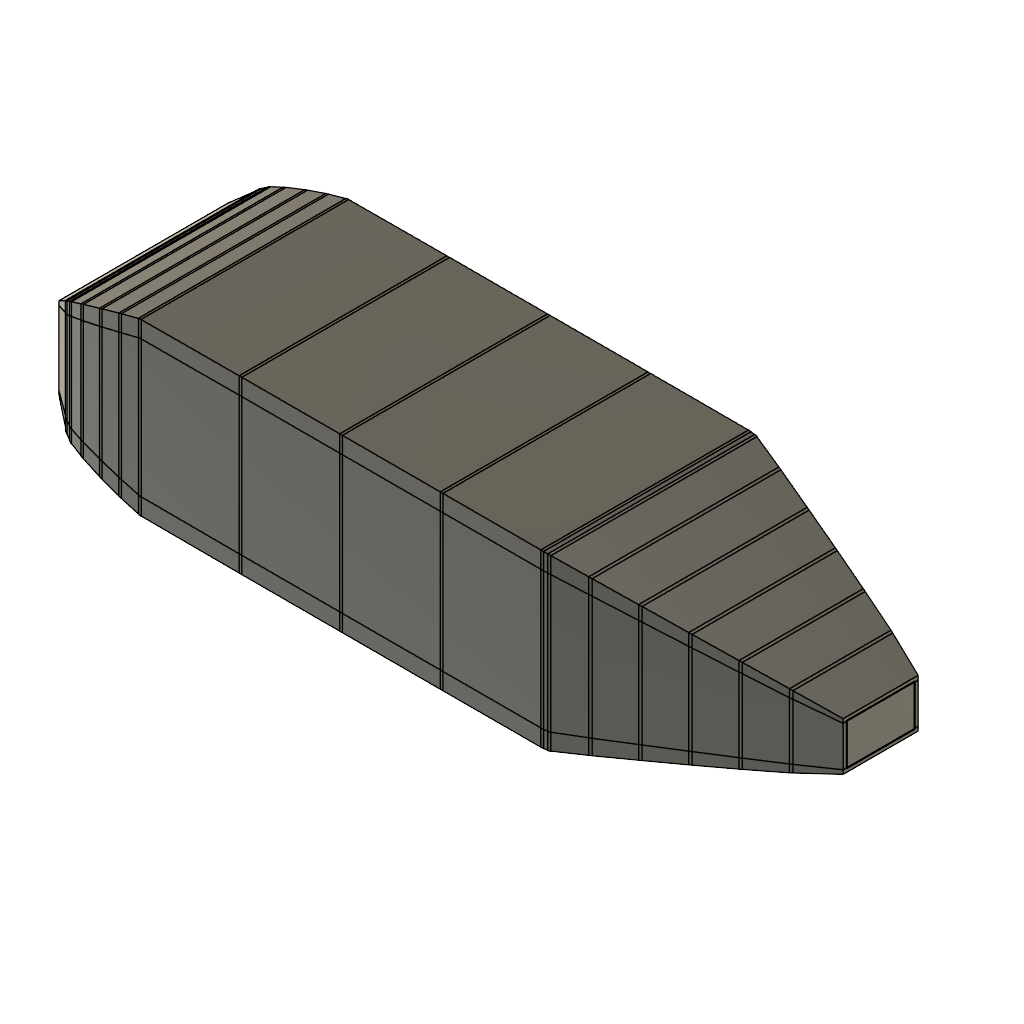
Magnetide-B-printable (Autodesk Fusion 360 design; units mm, degrees)
part number: 2026-10-21-01-27-55-911
Autodesk Fusion 360 part; units mm, degrees
(part 1 of 2)
ref_plane "WorkPlane1" through (60, 0, 0) normal (1, 0, 0) x (0, 1, 0)
sketch "plate_a" plane through (60, 0, 0) normal (1, 0, 0) x (0, 0, -1)
  line L0 (-7, -21.85) -> (-7, 21.85)
  line L1 (-7, 21.85) -> (-10.5, 21.85)
  line L2 (-10.5, 21.85) -> (-10.5, 22.75)
  line L3 (-10.5, 22.75) -> (-7, 22.75)
  line L4 (-7, 22.75) -> (-7, 23.5)
  line L5 (-7, 23.5) -> (-18.5, 23.5)
  line L6 (-18.5, 23.5) -> (-18.5, 20.3)
  line L7 (-18.5, 20.3) -> (-8.5, 20.3)
  line L8 (-8.5, 20.3) -> (-8.5, -20.3)
  line L9 (-8.5, -20.3) -> (-18.5, -20.3)
  line L10 (-18.5, -20.3) -> (-18.5, -23.5)
  line L11 (-18.5, -23.5) -> (-7, -23.5)
  line L12 (-7, -23.5) -> (-7, -22.75)
  line L13 (-7, -22.75) -> (-10.5, -22.75)
  line L14 (-10.5, -22.75) -> (-10.5, -21.85)
  line L15 (-10.5, -21.85) -> (-7, -21.85)
extrude "Extrude1" add sketch "plate_a" along normal mid plane 120 makes body 1
ref_plane "WorkPlane2" through (60, 0, 0) normal (1, 0, 0) x (0, 1, 0)
sketch "plate_b" plane through (60, 0, 0) normal (1, 0, 0) x (0, 0, -1)
  line L0 (7, -21.85) -> (7, 21.85)
  line L1 (7, 21.85) -> (10.5, 21.85)
  line L2 (10.5, 21.85) -> (10.5, 22.75)
  line L3 (10.5, 22.75) -> (7, 22.75)
  line L4 (7, 22.75) -> (7, 23.5)
  line L5 (7, 23.5) -> (18.5, 23.5)
  line L6 (18.5, 23.5) -> (18.5, 20.3)
  line L7 (18.5, 20.3) -> (8.5, 20.3)
  line L8 (8.5, 20.3) -> (8.5, -20.3)
  line L9 (8.5, -20.3) -> (18.5, -20.3)
  line L10 (18.5, -20.3) -> (18.5, -23.5)
  line L11 (18.5, -23.5) -> (7, -23.5)
  line L12 (7, -23.5) -> (7, -22.75)
  line L13 (7, -22.75) -> (10.5, -22.75)
  line L14 (10.5, -22.75) -> (10.5, -21.85)
  line L15 (10.5, -21.85) -> (7, -21.85)
extrude "Extrude2" add sketch "plate_b" along normal mid plane 120 separate body makes body 2
ref_plane "WorkPlane3" through (0, -22.7, 0) normal (0, 1, 0) x (0, 0, 1)
sketch "rail_left" plane through (0, -22.7, 0) normal (0, 1, 0) x (1, 0, 0)
  line L0 (0, 7) -> (120, 7)
  line L1 (120, 7) -> (120, -7)
  line L2 (120, -7) -> (0, -7)
  line L3 (0, -7) -> (0, 7)
extrude "Extrude3" add sketch "rail_left" along normal mid plane 1.6 separate body makes body 3
ref_plane "WorkPlane4" through (0, 22.7, 0) normal (0, 1, 0) x (0, 0, 1)
sketch "rail_right" plane through (0, 22.7, 0) normal (0, 1, 0) x (1, 0, 0)
  line L0 (0, 7) -> (120, 7)
  line L1 (120, 7) -> (120, -7)
  line L2 (120, -7) -> (0, -7)
  line L3 (0, -7) -> (0, 7)
extrude "Extrude4" add sketch "rail_right" along normal mid plane 1.6 separate body makes body 4
ref_plane "WorkPlane5" through (-20, 0, 0) normal (1, 0, 0) x (0, 1, 0)
sketch "Sketch5" plane through (-20, 0, 0) normal (1, 0, 0) x (0, 0, -1)
  line L0 (-12, -23.5) -> (-10.5, -23.5)
  line L1 (-10.5, -23.5) -> (-10.5, 23.5)
  line L2 (-10.5, 23.5) -> (-12, 23.5)
  line L3 (-12, 23.5) -> (-12, -23.5)
ref_plane "WorkPlane6" through (-15.6, 0, 0) normal (1, 0, 0) x (0, 1, 0)
sketch "Sketch6" plane through (-15.6, 0, 0) normal (1, 0, 0) x (0, 0, -1)
  line L0 (-10.6294, -23.5) -> (-9.1294, -23.5)
  line L1 (-9.1294, -23.5) -> (-9.1294, 23.5)
  line L2 (-9.1294, 23.5) -> (-10.6294, 23.5)
  line L3 (-10.6294, 23.5) -> (-10.6294, -23.5)
loft "Loft1" add profiles "Sketch5", "Sketch6" section 1 section 2 separate body makes body 5
ref_plane "WorkPlane7" through (-16.4, 0, 0) normal (1, 0, 0) x (0, 1, 0)
sketch "Sketch7" plane through (-16.4, 0, 0) normal (1, 0, 0) x (0, 0, -1)
  line L0 (-10.8534, -23.5) -> (-9.3534, -23.5)
  line L1 (-9.3534, -23.5) -> (-9.3534, 23.5)
  line L2 (-9.3534, 23.5) -> (-10.8534, 23.5)
  line L3 (-10.8534, 23.5) -> (-10.8534, -23.5)
ref_plane "WorkPlane8" through (-11.6, 0, 0) normal (1, 0, 0) x (0, 1, 0)
sketch "Sketch8" plane through (-11.6, 0, 0) normal (1, 0, 0) x (0, 0, -1)
  line L0 (-9.6774, -23.5) -> (-8.1774, -23.5)
  line L1 (-8.1774, -23.5) -> (-8.1774, 23.5)
  line L2 (-8.1774, 23.5) -> (-9.6774, 23.5)
  line L3 (-9.6774, 23.5) -> (-9.6774, -23.5)
loft "Loft2" add profiles "Sketch7", "Sketch8" section 1 section 2 separate body makes body 6
ref_plane "WorkPlane9" through (-12.4, 0, 0) normal (1, 0, 0) x (0, 1, 0)
sketch "Sketch9" plane through (-12.4, 0, 0) normal (1, 0, 0) x (0, 0, -1)
  line L0 (-9.8454, -23.5) -> (-8.3454, -23.5)
  line L1 (-8.3454, -23.5) -> (-8.3454, 23.5)
  line L2 (-8.3454, 23.5) -> (-9.8454, 23.5)
  line L3 (-9.8454, 23.5) -> (-9.8454, -23.5)
ref_plane "WorkPlane10" through (-7.6, 0, 0) normal (1, 0, 0) x (0, 1, 0)
sketch "Sketch10" plane through (-7.6, 0, 0) normal (1, 0, 0) x (0, 0, -1)
  line L0 (-9.0054, -23.5) -> (-7.5054, -23.5)
  line L1 (-7.5054, -23.5) -> (-7.5054, 23.5)
  line L2 (-7.5054, 23.5) -> (-9.0054, 23.5)
  line L3 (-9.0054, 23.5) -> (-9.0054, -23.5)
loft "Loft3" add profiles "Sketch9", "Sketch10" section 1 section 2 separate body makes body 7
ref_plane "WorkPlane11" through (-8.4, 0, 0) normal (1, 0, 0) x (0, 1, 0)
sketch "Sketch11" plane through (-8.4, 0, 0) normal (1, 0, 0) x (0, 0, -1)
  line L0 (-9.1174, -23.5) -> (-7.6174, -23.5)
  line L1 (-7.6174, -23.5) -> (-7.6174, 23.5)
  line L2 (-7.6174, 23.5) -> (-9.1174, 23.5)
  line L3 (-9.1174, 23.5) -> (-9.1174, -23.5)
ref_plane "WorkPlane12" through (-3.6, 0, 0) normal (1, 0, 0) x (0, 1, 0)
sketch "Sketch12" plane through (-3.6, 0, 0) normal (1, 0, 0) x (0, 0, -1)
  line L0 (-8.6134, -23.5) -> (-7.1134, -23.5)
  line L1 (-7.1134, -23.5) -> (-7.1134, 23.5)
  line L2 (-7.1134, 23.5) -> (-8.6134, 23.5)
  line L3 (-8.6134, 23.5) -> (-8.6134, -23.5)
loft "Loft4" add profiles "Sketch11", "Sketch12" section 1 section 2 separate body makes body 8
ref_plane "WorkPlane13" through (-4.4, 0, 0) normal (1, 0, 0) x (0, 1, 0)
sketch "Sketch13" plane through (-4.4, 0, 0) normal (1, 0, 0) x (0, 0, -1)
  line L0 (-8.6694, -23.5) -> (-7.1694, -23.5)
  line L1 (-7.1694, -23.5) -> (-7.1694, 23.5)
  line L2 (-7.1694, 23.5) -> (-8.6694, 23.5)
  line L3 (-8.6694, 23.5) -> (-8.6694, -23.5)
ref_plane "WorkPlane14" through (0, 0, 0) normal (1, 0, 0) x (0, 1, 0)
sketch "Sketch14" plane through (0, 0, 0) normal (1, 0, 0) x (0, 0, -1)
  line L0 (-8.5, -23.5) -> (-7, -23.5)
  line L1 (-7, -23.5) -> (-7, 23.5)
  line L2 (-7, 23.5) -> (-8.5, 23.5)
  line L3 (-8.5, 23.5) -> (-8.5, -23.5)
loft "Loft5" add profiles "Sketch13", "Sketch14" section 1 section 2 separate body makes body 9
ref_plane "WorkPlane15" through (-20, 0, 0) normal (1, 0, 0) x (0, 1, 0)
sketch "Sketch15" plane through (-20, 0, 0) normal (1, 0, 0) x (0, 0, -1)
  line L0 (10.5, -23.5) -> (12, -23.5)
  line L1 (12, -23.5) -> (12, 23.5)
  line L2 (12, 23.5) -> (10.5, 23.5)
  line L3 (10.5, 23.5) -> (10.5, -23.5)
ref_plane "WorkPlane16" through (-15.6, 0, 0) normal (1, 0, 0) x (0, 1, 0)
sketch "Sketch16" plane through (-15.6, 0, 0) normal (1, 0, 0) x (0, 0, -1)
  line L0 (9.1294, -23.5) -> (10.6294, -23.5)
  line L1 (10.6294, -23.5) -> (10.6294, 23.5)
  line L2 (10.6294, 23.5) -> (9.1294, 23.5)
  line L3 (9.1294, 23.5) -> (9.1294, -23.5)
loft "Loft6" add profiles "Sketch15", "Sketch16" section 1 section 2 separate body makes body 10
ref_plane "WorkPlane17" through (-16.4, 0, 0) normal (1, 0, 0) x (0, 1, 0)
sketch "Sketch17" plane through (-16.4, 0, 0) normal (1, 0, 0) x (0, 0, -1)
  line L0 (9.3534, -23.5) -> (10.8534, -23.5)
  line L1 (10.8534, -23.5) -> (10.8534, 23.5)
  line L2 (10.8534, 23.5) -> (9.3534, 23.5)
  line L3 (9.3534, 23.5) -> (9.3534, -23.5)
ref_plane "WorkPlane18" through (-11.6, 0, 0) normal (1, 0, 0) x (0, 1, 0)
sketch "Sketch18" plane through (-11.6, 0, 0) normal (1, 0, 0) x (0, 0, -1)
  line L0 (8.1774, -23.5) -> (9.6774, -23.5)
  line L1 (9.6774, -23.5) -> (9.6774, 23.5)
  line L2 (9.6774, 23.5) -> (8.1774, 23.5)
  line L3 (8.1774, 23.5) -> (8.1774, -23.5)
loft "Loft7" add profiles "Sketch17", "Sketch18" section 1 section 2 separate body makes body 11
ref_plane "WorkPlane19" through (-12.4, 0, 0) normal (1, 0, 0) x (0, 1, 0)
sketch "Sketch19" plane through (-12.4, 0, 0) normal (1, 0, 0) x (0, 0, -1)
  line L0 (8.3454, -23.5) -> (9.8454, -23.5)
  line L1 (9.8454, -23.5) -> (9.8454, 23.5)
  line L2 (9.8454, 23.5) -> (8.3454, 23.5)
  line L3 (8.3454, 23.5) -> (8.3454, -23.5)
ref_plane "WorkPlane20" through (-7.6, 0, 0) normal (1, 0, 0) x (0, 1, 0)
sketch "Sketch20" plane through (-7.6, 0, 0) normal (1, 0, 0) x (0, 0, -1)
  line L0 (7.5054, -23.5) -> (9.0054, -23.5)
  line L1 (9.0054, -23.5) -> (9.0054, 23.5)
  line L2 (9.0054, 23.5) -> (7.5054, 23.5)
  line L3 (7.5054, 23.5) -> (7.5054, -23.5)
loft "Loft8" add profiles "Sketch19", "Sketch20" section 1 section 2 separate body makes body 12
ref_plane "WorkPlane21" through (-8.4, 0, 0) normal (1, 0, 0) x (0, 1, 0)
sketch "Sketch21" plane through (-8.4, 0, 0) normal (1, 0, 0) x (0, 0, -1)
  line L0 (7.6174, -23.5) -> (9.1174, -23.5)
  line L1 (9.1174, -23.5) -> (9.1174, 23.5)
  line L2 (9.1174, 23.5) -> (7.6174, 23.5)
  line L3 (7.6174, 23.5) -> (7.6174, -23.5)
ref_plane "WorkPlane22" through (-3.6, 0, 0) normal (1, 0, 0) x (0, 1, 0)
sketch "Sketch22" plane through (-3.6, 0, 0) normal (1, 0, 0) x (0, 0, -1)
  line L0 (7.1134, -23.5) -> (8.6134, -23.5)
  line L1 (8.6134, -23.5) -> (8.6134, 23.5)
  line L2 (8.6134, 23.5) -> (7.1134, 23.5)
  line L3 (7.1134, 23.5) -> (7.1134, -23.5)
loft "Loft9" add profiles "Sketch21", "Sketch22" section 1 section 2 separate body makes body 13
ref_plane "WorkPlane23" through (-4.4, 0, 0) normal (1, 0, 0) x (0, 1, 0)
sketch "Sketch23" plane through (-4.4, 0, 0) normal (1, 0, 0) x (0, 0, -1)
  line L0 (7.1694, -23.5) -> (8.6694, -23.5)
  line L1 (8.6694, -23.5) -> (8.6694, 23.5)
  line L2 (8.6694, 23.5) -> (7.1694, 23.5)
  line L3 (7.1694, 23.5) -> (7.1694, -23.5)
ref_plane "WorkPlane24" through (0, 0, 0) normal (1, 0, 0) x (0, 1, 0)
sketch "Sketch24" plane through (0, 0, 0) normal (1, 0, 0) x (0, 0, -1)
  line L0 (7, -23.5) -> (8.5, -23.5)
  line L1 (8.5, -23.5) -> (8.5, 23.5)
  line L2 (8.5, 23.5) -> (7, 23.5)
  line L3 (7, 23.5) -> (7, -23.5)
loft "Loft10" add profiles "Sketch23", "Sketch24" section 1 section 2 separate body makes body 14
ref_plane "WorkPlane25" through (-20, 0, 0) normal (1, 0, 0) x (0, 1, 0)
sketch "Sketch25" plane through (-20, 0, 0) normal (1, 0, 0) x (0, 0, -1)
  line L0 (-10.5, -23.5) -> (10.5, -23.5)
  line L1 (10.5, -23.5) -> (10.5, -21.5)
  line L2 (10.5, -21.5) -> (-10.5, -21.5)
  line L3 (-10.5, -21.5) -> (-10.5, -23.5)
ref_plane "WorkPlane26" through (-15.6, 0, 0) normal (1, 0, 0) x (0, 1, 0)
sketch "Sketch26" plane through (-15.6, 0, 0) normal (1, 0, 0) x (0, 0, -1)
  line L0 (-9.1294, -23.5) -> (9.1294, -23.5)
  line L1 (9.1294, -23.5) -> (9.1294, -21.5)
  line L2 (9.1294, -21.5) -> (-9.1294, -21.5)
  line L3 (-9.1294, -21.5) -> (-9.1294, -23.5)
loft "Loft11" add profiles "Sketch25", "Sketch26" section 1 section 2 separate body makes body 15
ref_plane "WorkPlane27" through (-16.4, 0, 0) normal (1, 0, 0) x (0, 1, 0)
sketch "Sketch27" plane through (-16.4, 0, 0) normal (1, 0, 0) x (0, 0, -1)
  line L0 (-9.3534, -23.5) -> (9.3534, -23.5)
  line L1 (9.3534, -23.5) -> (9.3534, -21.5)
  line L2 (9.3534, -21.5) -> (-9.3534, -21.5)
  line L3 (-9.3534, -21.5) -> (-9.3534, -23.5)
ref_plane "WorkPlane28" through (-11.6, 0, 0) normal (1, 0, 0) x (0, 1, 0)
sketch "Sketch28" plane through (-11.6, 0, 0) normal (1, 0, 0) x (0, 0, -1)
  line L0 (-8.1774, -23.5) -> (8.1774, -23.5)
  line L1 (8.1774, -23.5) -> (8.1774, -21.5)
  line L2 (8.1774, -21.5) -> (-8.1774, -21.5)
  line L3 (-8.1774, -21.5) -> (-8.1774, -23.5)
loft "Loft12" add profiles "Sketch27", "Sketch28" section 1 section 2 separate body makes body 16
ref_plane "WorkPlane29" through (-12.4, 0, 0) normal (1, 0, 0) x (0, 1, 0)
sketch "Sketch29" plane through (-12.4, 0, 0) normal (1, 0, 0) x (0, 0, -1)
  line L0 (-8.3454, -23.5) -> (8.3454, -23.5)
  line L1 (8.3454, -23.5) -> (8.3454, -21.5)
  line L2 (8.3454, -21.5) -> (-8.3454, -21.5)
  line L3 (-8.3454, -21.5) -> (-8.3454, -23.5)
ref_plane "WorkPlane30" through (-7.6, 0, 0) normal (1, 0, 0) x (0, 1, 0)
sketch "Sketch30" plane through (-7.6, 0, 0) normal (1, 0, 0) x (0, 0, -1)
  line L0 (-7.5054, -23.5) -> (7.5054, -23.5)
  line L1 (7.5054, -23.5) -> (7.5054, -21.5)
  line L2 (7.5054, -21.5) -> (-7.5054, -21.5)
  line L3 (-7.5054, -21.5) -> (-7.5054, -23.5)
loft "Loft13" add profiles "Sketch29", "Sketch30" section 1 section 2 separate body makes body 17
ref_plane "WorkPlane31" through (-8.4, 0, 0) normal (1, 0, 0) x (0, 1, 0)
sketch "Sketch31" plane through (-8.4, 0, 0) normal (1, 0, 0) x (0, 0, -1)
  line L0 (-7.6174, -23.5) -> (7.6174, -23.5)
  line L1 (7.6174, -23.5) -> (7.6174, -21.5)
  line L2 (7.6174, -21.5) -> (-7.6174, -21.5)
  line L3 (-7.6174, -21.5) -> (-7.6174, -23.5)
ref_plane "WorkPlane32" through (-3.6, 0, 0) normal (1, 0, 0) x (0, 1, 0)
sketch "Sketch32" plane through (-3.6, 0, 0) normal (1, 0, 0) x (0, 0, -1)
  line L0 (-7.1134, -23.5) -> (7.1134, -23.5)
  line L1 (7.1134, -23.5) -> (7.1134, -21.5)
  line L2 (7.1134, -21.5) -> (-7.1134, -21.5)
  line L3 (-7.1134, -21.5) -> (-7.1134, -23.5)
loft "Loft14" add profiles "Sketch31", "Sketch32" section 1 section 2 separate body makes body 18
ref_plane "WorkPlane33" through (-4.4, 0, 0) normal (1, 0, 0) x (0, 1, 0)
sketch "Sketch33" plane through (-4.4, 0, 0) normal (1, 0, 0) x (0, 0, -1)
  line L0 (-7.1694, -23.5) -> (7.1694, -23.5)
  line L1 (7.1694, -23.5) -> (7.1694, -21.5)
  line L2 (7.1694, -21.5) -> (-7.1694, -21.5)
  line L3 (-7.1694, -21.5) -> (-7.1694, -23.5)
ref_plane "WorkPlane34" through (0, 0, 0) normal (1, 0, 0) x (0, 1, 0)
sketch "Sketch34" plane through (0, 0, 0) normal (1, 0, 0) x (0, 0, -1)
  line L0 (-7, -23.5) -> (7, -23.5)
  line L1 (7, -23.5) -> (7, -21.5)
  line L2 (7, -21.5) -> (-7, -21.5)
  line L3 (-7, -21.5) -> (-7, -23.5)
loft "Loft15" add profiles "Sketch33", "Sketch34" section 1 section 2 separate body makes body 19
ref_plane "WorkPlane35" through (-20, 0, 0) normal (1, 0, 0) x (0, 1, 0)
sketch "Sketch35" plane through (-20, 0, 0) normal (1, 0, 0) x (0, 0, -1)
  line L0 (-10.5, 21.5) -> (10.5, 21.5)
  line L1 (10.5, 21.5) -> (10.5, 23.5)
  line L2 (10.5, 23.5) -> (-10.5, 23.5)
  line L3 (-10.5, 23.5) -> (-10.5, 21.5)
ref_plane "WorkPlane36" through (-15.6, 0, 0) normal (1, 0, 0) x (0, 1, 0)
sketch "Sketch36" plane through (-15.6, 0, 0) normal (1, 0, 0) x (0, 0, -1)
  line L0 (-9.1294, 21.5) -> (9.1294, 21.5)
  line L1 (9.1294, 21.5) -> (9.1294, 23.5)
  line L2 (9.1294, 23.5) -> (-9.1294, 23.5)
  line L3 (-9.1294, 23.5) -> (-9.1294, 21.5)
loft "Loft16" add profiles "Sketch35", "Sketch36" section 1 section 2 separate body makes body 20
ref_plane "WorkPlane37" through (-16.4, 0, 0) normal (1, 0, 0) x (0, 1, 0)
sketch "Sketch37" plane through (-16.4, 0, 0) normal (1, 0, 0) x (0, 0, -1)
  line L0 (-9.3534, 21.5) -> (9.3534, 21.5)
  line L1 (9.3534, 21.5) -> (9.3534, 23.5)
  line L2 (9.3534, 23.5) -> (-9.3534, 23.5)
  line L3 (-9.3534, 23.5) -> (-9.3534, 21.5)
ref_plane "WorkPlane38" through (-11.6, 0, 0) normal (1, 0, 0) x (0, 1, 0)
sketch "Sketch38" plane through (-11.6, 0, 0) normal (1, 0, 0) x (0, 0, -1)
  line L0 (-8.1774, 21.5) -> (8.1774, 21.5)
  line L1 (8.1774, 21.5) -> (8.1774, 23.5)
  line L2 (8.1774, 23.5) -> (-8.1774, 23.5)
  line L3 (-8.1774, 23.5) -> (-8.1774, 21.5)
loft "Loft17" add profiles "Sketch37", "Sketch38" section 1 section 2 separate body makes body 21
ref_plane "WorkPlane39" through (-12.4, 0, 0) normal (1, 0, 0) x (0, 1, 0)
sketch "Sketch39" plane through (-12.4, 0, 0) normal (1, 0, 0) x (0, 0, -1)
  line L0 (-8.3454, 21.5) -> (8.3454, 21.5)
  line L1 (8.3454, 21.5) -> (8.3454, 23.5)
  line L2 (8.3454, 23.5) -> (-8.3454, 23.5)
  line L3 (-8.3454, 23.5) -> (-8.3454, 21.5)
ref_plane "WorkPlane40" through (-7.6, 0, 0) normal (1, 0, 0) x (0, 1, 0)
sketch "Sketch40" plane through (-7.6, 0, 0) normal (1, 0, 0) x (0, 0, -1)
  line L0 (-7.5054, 21.5) -> (7.5054, 21.5)
  line L1 (7.5054, 21.5) -> (7.5054, 23.5)
  line L2 (7.5054, 23.5) -> (-7.5054, 23.5)
  line L3 (-7.5054, 23.5) -> (-7.5054, 21.5)
loft "Loft18" add profiles "Sketch39", "Sketch40" section 1 section 2 separate body makes body 22
ref_plane "WorkPlane41" through (-8.4, 0, 0) normal (1, 0, 0) x (0, 1, 0)
sketch "Sketch41" plane through (-8.4, 0, 0) normal (1, 0, 0) x (0, 0, -1)
  line L0 (-7.6174, 21.5) -> (7.6174, 21.5)
  line L1 (7.6174, 21.5) -> (7.6174, 23.5)
  line L2 (7.6174, 23.5) -> (-7.6174, 23.5)
  line L3 (-7.6174, 23.5) -> (-7.6174, 21.5)
ref_plane "WorkPlane42" through (-3.6, 0, 0) normal (1, 0, 0) x (0, 1, 0)
sketch "Sketch42" plane through (-3.6, 0, 0) normal (1, 0, 0) x (0, 0, -1)
  line L0 (-7.1134, 21.5) -> (7.1134, 21.5)
  line L1 (7.1134, 21.5) -> (7.1134, 23.5)
  line L2 (7.1134, 23.5) -> (-7.1134, 23.5)
  line L3 (-7.1134, 23.5) -> (-7.1134, 21.5)
loft "Loft19" add profiles "Sketch41", "Sketch42" section 1 section 2 separate body makes body 23
ref_plane "WorkPlane43" through (-4.4, 0, 0) normal (1, 0, 0) x (0, 1, 0)
sketch "Sketch43" plane through (-4.4, 0, 0) normal (1, 0, 0) x (0, 0, -1)
  line L0 (-7.1694, 21.5) -> (7.1694, 21.5)
  line L1 (7.1694, 21.5) -> (7.1694, 23.5)
  line L2 (7.1694, 23.5) -> (-7.1694, 23.5)
  line L3 (-7.1694, 23.5) -> (-7.1694, 21.5)
ref_plane "WorkPlane44" through (0, 0, 0) normal (1, 0, 0) x (0, 1, 0)
sketch "Sketch44" plane through (0, 0, 0) normal (1, 0, 0) x (0, 0, -1)
  line L0 (-7, 21.5) -> (7, 21.5)
  line L1 (7, 21.5) -> (7, 23.5)
  line L2 (7, 23.5) -> (-7, 23.5)
  line L3 (-7, 23.5) -> (-7, 21.5)
loft "Loft20" add profiles "Sketch43", "Sketch44" section 1 section 2 separate body makes body 24
ref_plane "WorkPlane45" through (-21, 0, 0) normal (1, 0, 0) x (0, 1, 0)
sketch "front_flange" plane through (-21, 0, 0) normal (1, 0, 0) x (0, 0, -1)
  line L0 (-14, -25.5) -> (14, -25.5)
  line L1 (14, -25.5) -> (14, 25.5)
  line L2 (14, 25.5) -> (-14, 25.5)
  line L3 (-14, 25.5) -> (-14, -25.5)
  line L4 (-10.5, -23.5) -> (-10.5, 23.5)
  line L5 (-10.5, 23.5) -> (10.5, 23.5)
  line L6 (10.5, 23.5) -> (10.5, -23.5)
  line L7 (10.5, -23.5) -> (-10.5, -23.5)
extrude "Extrude5" add sketch "front_flange" along normal mid plane 2 separate body makes body 25
ref_plane "WorkPlane46" through (121, 0, 0) normal (1, 0, 0) x (0, 1, 0)
sketch "rear_cap" plane through (121, 0, 0) normal (1, 0, 0) x (0, 0, -1)
  line L0 (-18.4, -25.5) -> (18.4, -25.5)
  line L1 (18.4, -25.5) -> (18.4, 25.5)
  line L2 (18.4, 25.5) -> (-18.4, 25.5)
  line L3 (-18.4, 25.5) -> (-18.4, -25.5)
  line L4 (-10.6, -23.6) -> (10.6, -23.6)
  line L5 (10.6, -23.6) -> (10.6, 23.6)
  line L6 (10.6, 23.6) -> (-10.6, 23.6)
  line L7 (-10.6, 23.6) -> (-10.6, -23.6)
extrude "Extrude6" add sketch "rear_cap" along normal mid plane 2 separate body makes body 26
ref_plane "WorkPlane47" through (-30, 0, 0) normal (1, 0, 0) x (0, 1, 0)
sketch "Sketch47" plane through (-30, 0, 0) normal (1, 0, 0) x (0, 0, -1)
  line L0 (-12.2, -25.2) -> (-11, -25.2)
  line L1 (-11, -25.2) -> (-11, 25.2)
  line L2 (-11, 25.2) -> (-12.2, 25.2)
  line L3 (-12.2, 25.2) -> (-12.2, -25.2)
ref_plane "WorkPlane48" through (-23.6, 0, 0) normal (1, 0, 0) x (0, 1, 0)
sketch "Sketch48" plane through (-23.6, 0, 0) normal (1, 0, 0) x (0, 0, -1)
  line L0 (-17.346, -29.146) -> (-13.8, -29.146)
  line L1 (-13.8, -29.146) -> (-13.8, 29.146)
  line L2 (-13.8, 29.146) -> (-17.346, 29.146)
  line L3 (-17.346, 29.146) -> (-17.346, -29.146)
loft "Loft21" add profiles "Sketch47", "Sketch48" section 1 section 2 separate body makes body 27
ref_plane "WorkPlane49" through (-24.4, 0, 0) normal (1, 0, 0) x (0, 1, 0)
sketch "Sketch49" plane through (-24.4, 0, 0) normal (1, 0, 0) x (0, 0, -1)
  line L0 (-16.8608, -28.8108) -> (-13.45, -28.8108)
  line L1 (-13.45, -28.8108) -> (-13.45, 28.8108)
  line L2 (-13.45, 28.8108) -> (-16.8608, 28.8108)
  line L3 (-16.8608, 28.8108) -> (-16.8608, -28.8108)
ref_plane "WorkPlane50" through (-21.6, 0, 0) normal (1, 0, 0) x (0, 1, 0)
sketch "Sketch50" plane through (-21.6, 0, 0) normal (1, 0, 0) x (0, 0, -1)
  line L0 (-18.4462, -29.8371) -> (-14.6091, -29.8371)
  line L1 (-14.6091, -29.8371) -> (-14.6091, 29.8371)
  line L2 (-14.6091, 29.8371) -> (-18.4462, 29.8371)
  line L3 (-18.4462, 29.8371) -> (-18.4462, -29.8371)
loft "Loft22" add profiles "Sketch49", "Sketch50" section 1 section 2 separate body makes body 28
ref_plane "WorkPlane51" through (-22.4, 0, 0) normal (1, 0, 0) x (0, 1, 0)
sketch "Sketch51" plane through (-22.4, 0, 0) normal (1, 0, 0) x (0, 0, -1)
  line L0 (-18.0528, -29.6278) -> (-14.325, -29.6278)
  line L1 (-14.325, -29.6278) -> (-14.325, 29.6278)
  line L2 (-14.325, 29.6278) -> (-18.0528, 29.6278)
  line L3 (-18.0528, 29.6278) -> (-18.0528, -29.6278)
ref_plane "WorkPlane52" through (-17.6, 0, 0) normal (1, 0, 0) x (0, 1, 0)
sketch "Sketch52" plane through (-17.6, 0, 0) normal (1, 0, 0) x (0, 0, -1)
  line L0 (-19.9773, -30.2773) -> (-15.7, -30.2773)
  line L1 (-15.7, -30.2773) -> (-15.7, 30.2773)
  line L2 (-15.7, 30.2773) -> (-19.9773, 30.2773)
  line L3 (-19.9773, 30.2773) -> (-19.9773, -30.2773)
loft "Loft23" add profiles "Sketch51", "Sketch52" section 1 section 2 separate body makes body 29
ref_plane "WorkPlane53" through (-18.4, 0, 0) normal (1, 0, 0) x (0, 1, 0)
sketch "Sketch53" plane through (-18.4, 0, 0) normal (1, 0, 0) x (0, 0, -1)
  line L0 (-19.6832, -30.2013) -> (-15.4818, -30.2013)
  line L1 (-15.4818, -30.2013) -> (-15.4818, 30.2013)
  line L2 (-15.4818, 30.2013) -> (-19.6832, 30.2013)
  line L3 (-19.6832, 30.2013) -> (-19.6832, -30.2013)
ref_plane "WorkPlane54" through (-11.6, 0, 0) normal (1, 0, 0) x (0, 1, 0)
sketch "Sketch54" plane through (-11.6, 0, 0) normal (1, 0, 0) x (0, 0, -1)
  line L0 (-22.0408, -30.7044) -> (-17.3364, -30.7044)
  line L1 (-17.3364, -30.7044) -> (-17.3364, 30.7044)
  line L2 (-17.3364, 30.7044) -> (-22.0408, 30.7044)
  line L3 (-22.0408, 30.7044) -> (-22.0408, -30.7044)
loft "Loft24" add profiles "Sketch53", "Sketch54" section 1 section 2 separate body makes body 30
ref_plane "WorkPlane55" through (-12.4, 0, 0) normal (1, 0, 0) x (0, 1, 0)
sketch "Sketch55" plane through (-12.4, 0, 0) normal (1, 0, 0) x (0, 0, -1)
  line L0 (-21.7784, -30.6602) -> (-17.1182, -30.6602)
  line L1 (-17.1182, -30.6602) -> (-17.1182, 30.6602)
  line L2 (-17.1182, 30.6602) -> (-21.7784, 30.6602)
  line L3 (-21.7784, 30.6602) -> (-21.7784, -30.6602)
ref_plane "WorkPlane56" through (-5.6, 0, 0) normal (1, 0, 0) x (0, 1, 0)
sketch "Sketch56" plane through (-5.6, 0, 0) normal (1, 0, 0) x (0, 0, -1)
  line L0 (-23.9059, -30.9332) -> (-18.9727, -30.9332)
  line L1 (-18.9727, -30.9332) -> (-18.9727, 30.9332)
  line L2 (-18.9727, 30.9332) -> (-23.9059, 30.9332)
  line L3 (-23.9059, 30.9332) -> (-23.9059, -30.9332)
loft "Loft25" add profiles "Sketch55", "Sketch56" section 1 section 2 separate body makes body 31
ref_plane "WorkPlane57" through (-6.4, 0, 0) normal (1, 0, 0) x (0, 1, 0)
sketch "Sketch57" plane through (-6.4, 0, 0) normal (1, 0, 0) x (0, 0, -1)
  line L0 (-23.6671, -30.9125) -> (-18.7545, -30.9125)
  line L1 (-18.7545, -30.9125) -> (-18.7545, 30.9125)
  line L2 (-18.7545, 30.9125) -> (-23.6671, 30.9125)
  line L3 (-23.6671, 30.9125) -> (-23.6671, -30.9125)
ref_plane "WorkPlane58" through (0.4, 0, 0) normal (1, 0, 0) x (0, 1, 0)
sketch "Sketch58" plane through (0.4, 0, 0) normal (1, 0, 0) x (0, 0, -1)
  line L0 (-25.5, -31) -> (-20.5, -31)
  line L1 (-20.5, -31) -> (-20.5, 31)
  line L2 (-20.5, 31) -> (-25.5, 31)
  line L3 (-25.5, 31) -> (-25.5, -31)
loft "Loft26" add profiles "Sketch57", "Sketch58" section 1 section 2 separate body makes body 32
ref_plane "WorkPlane59" through (-0.4, 0, 0) normal (1, 0, 0) x (0, 1, 0)
sketch "Sketch59" plane through (-0.4, 0, 0) normal (1, 0, 0) x (0, 0, -1)
  line L0 (-25.3906, -30.9997) -> (-20.3909, -30.9997)
  line L1 (-20.3909, -30.9997) -> (-20.3909, 30.9997)
  line L2 (-20.3909, 30.9997) -> (-25.3906, 30.9997)
  line L3 (-25.3906, 30.9997) -> (-25.3906, -30.9997)
ref_plane "WorkPlane60" through (30.4, 0, 0) normal (1, 0, 0) x (0, 1, 0)
sketch "Sketch60" plane through (30.4, 0, 0) normal (1, 0, 0) x (0, 0, -1)
  line L0 (-25.5, -31) -> (-20.5, -31)
  line L1 (-20.5, -31) -> (-20.5, 31)
  line L2 (-20.5, 31) -> (-25.5, 31)
  line L3 (-25.5, 31) -> (-25.5, -31)
loft "Loft27" add profiles "Sketch59", "Sketch60" section 1 section 2 separate body makes body 33
ref_plane "WorkPlane61" through (29.6, 0, 0) normal (1, 0, 0) x (0, 1, 0)
sketch "Sketch61" plane through (29.6, 0, 0) normal (1, 0, 0) x (0, 0, -1)
  line L0 (-25.5, -31) -> (-20.5, -31)
  line L1 (-20.5, -31) -> (-20.5, 31)
  line L2 (-20.5, 31) -> (-25.5, 31)
  line L3 (-25.5, 31) -> (-25.5, -31)
ref_plane "WorkPlane62" through (60.4, 0, 0) normal (1, 0, 0) x (0, 1, 0)
sketch "Sketch62" plane through (60.4, 0, 0) normal (1, 0, 0) x (0, 0, -1)
  line L0 (-25.5, -31) -> (-20.5, -31)
  line L1 (-20.5, -31) -> (-20.5, 31)
  line L2 (-20.5, 31) -> (-25.5, 31)
  line L3 (-25.5, 31) -> (-25.5, -31)
loft "Loft28" add profiles "Sketch61", "Sketch62" section 1 section 2 separate body makes body 34
ref_plane "WorkPlane63" through (59.6, 0, 0) normal (1, 0, 0) x (0, 1, 0)
sketch "Sketch63" plane through (59.6, 0, 0) normal (1, 0, 0) x (0, 0, -1)
  line L0 (-25.5, -31) -> (-20.5, -31)
  line L1 (-20.5, -31) -> (-20.5, 31)
  line L2 (-20.5, 31) -> (-25.5, 31)
  line L3 (-25.5, 31) -> (-25.5, -31)
ref_plane "WorkPlane64" through (90.4, 0, 0) normal (1, 0, 0) x (0, 1, 0)
sketch "Sketch64" plane through (90.4, 0, 0) normal (1, 0, 0) x (0, 0, -1)
  line L0 (-25.5, -31) -> (-20.5, -31)
  line L1 (-20.5, -31) -> (-20.5, 31)
  line L2 (-20.5, 31) -> (-25.5, 31)
  line L3 (-25.5, 31) -> (-25.5, -31)
loft "Loft29" add profiles "Sketch63", "Sketch64" section 1 section 2 separate body makes body 35
ref_plane "WorkPlane65" through (89.6, 0, 0) normal (1, 0, 0) x (0, 1, 0)
sketch "Sketch65" plane through (89.6, 0, 0) normal (1, 0, 0) x (0, 0, -1)
  line L0 (-25.5, -31) -> (-20.5, -31)
  line L1 (-20.5, -31) -> (-20.5, 31)
  line L2 (-20.5, 31) -> (-25.5, 31)
  line L3 (-25.5, 31) -> (-25.5, -31)
ref_plane "WorkPlane66" through (120.4, 0, 0) normal (1, 0, 0) x (0, 1, 0)
sketch "Sketch66" plane through (120.4, 0, 0) normal (1, 0, 0) x (0, 0, -1)
  line L0 (-25.4848, -30.9848) -> (-20.5, -30.9848)
  line L1 (-20.5, -30.9848) -> (-20.5, 30.9848)
  line L2 (-20.5, 30.9848) -> (-25.4848, 30.9848)
  line L3 (-25.4848, 30.9848) -> (-25.4848, -30.9848)
loft "Loft30" add profiles "Sketch65", "Sketch66" section 1 section 2 separate body makes body 36
ref_plane "WorkPlane67" through (119.6, 0, 0) normal (1, 0, 0) x (0, 1, 0)
sketch "Sketch67" plane through (119.6, 0, 0) normal (1, 0, 0) x (0, 0, -1)
  line L0 (-25.5, -31) -> (-20.5, -31)
  line L1 (-20.5, -31) -> (-20.5, 31)
  line L2 (-20.5, 31) -> (-25.5, 31)
  line L3 (-25.5, 31) -> (-25.5, -31)
ref_plane "WorkPlane68" through (122.4, 0, 0) normal (1, 0, 0) x (0, 1, 0)
sketch "Sketch68" plane through (122.4, 0, 0) normal (1, 0, 0) x (0, 0, -1)
  line L0 (-25.323, -30.8142) -> (-20.4147, -30.8142)
  line L1 (-20.4147, -30.8142) -> (-20.4147, 30.8142)
  line L2 (-20.4147, 30.8142) -> (-25.323, 30.8142)
  line L3 (-25.323, 30.8142) -> (-25.323, -30.8142)
loft "Loft31" add profiles "Sketch67", "Sketch68" section 1 section 2 separate body makes body 37
ref_plane "WorkPlane69" through (121.6, 0, 0) normal (1, 0, 0) x (0, 1, 0)
sketch "Sketch69" plane through (121.6, 0, 0) normal (1, 0, 0) x (0, 0, -1)
  line L0 (-25.439, -30.939) -> (-20.5, -30.939)
  line L1 (-20.5, -30.939) -> (-20.5, 30.939)
  line L2 (-20.5, 30.939) -> (-25.439, 30.939)
  line L3 (-25.439, 30.939) -> (-25.439, -30.939)
ref_plane "WorkPlane70" through (132.0667, 0, 0) normal (1, 0, 0) x (0, 1, 0)
sketch "Sketch70" plane through (132.0667, 0, 0) normal (1, 0, 0) x (0, 0, -1)
  line L0 (-22.8821, -28.16) -> (-18.3534, -28.16)
  line L1 (-18.3534, -28.16) -> (-18.3534, 28.16)
  line L2 (-18.3534, 28.16) -> (-22.8821, 28.16)
  line L3 (-22.8821, 28.16) -> (-22.8821, -28.16)
loft "Loft32" add profiles "Sketch69", "Sketch70" section 1 section 2 separate body makes body 38
ref_plane "WorkPlane71" through (131.2667, 0, 0) normal (1, 0, 0) x (0, 1, 0)
sketch "Sketch71" plane through (131.2667, 0, 0) normal (1, 0, 0) x (0, 0, -1)
  line L0 (-23.0848, -28.3803) -> (-18.524, -28.3803)
  line L1 (-18.524, -28.3803) -> (-18.524, 28.3803)
  line L2 (-18.524, 28.3803) -> (-23.0848, 28.3803)
  line L3 (-23.0848, 28.3803) -> (-23.0848, -28.3803)
ref_plane "WorkPlane72" through (143.7333, 0, 0) normal (1, 0, 0) x (0, 1, 0)
sketch "Sketch72" plane through (143.7333, 0, 0) normal (1, 0, 0) x (0, 0, -1)
  line L0 (-19.9095, -24.9301) -> (-15.8657, -24.9301)
  line L1 (-15.8657, -24.9301) -> (-15.8657, 24.9301)
  line L2 (-15.8657, 24.9301) -> (-19.9095, 24.9301)
  line L3 (-19.9095, 24.9301) -> (-19.9095, -24.9301)
loft "Loft33" add profiles "Sketch71", "Sketch72" section 1 section 2 separate body makes body 39
ref_plane "WorkPlane73" through (142.9333, 0, 0) normal (1, 0, 0) x (0, 1, 0)
sketch "Sketch73" plane through (142.9333, 0, 0) normal (1, 0, 0) x (0, 0, -1)
  line L0 (-20.1144, -25.1527) -> (-16.0363, -25.1527)
  line L1 (-16.0363, -25.1527) -> (-16.0363, 25.1527)
  line L2 (-16.0363, 25.1527) -> (-20.1144, 25.1527)
  line L3 (-20.1144, 25.1527) -> (-20.1144, -25.1527)
ref_plane "WorkPlane74" through (155.4, 0, 0) normal (1, 0, 0) x (0, 1, 0)
sketch "Sketch74" plane through (155.4, 0, 0) normal (1, 0, 0) x (0, 0, -1)
  line L0 (-16.8984, -21.6616) -> (-13.3779, -21.6616)
  line L1 (-13.3779, -21.6616) -> (-13.3779, 21.6616)
  line L2 (-13.3779, 21.6616) -> (-16.8984, 21.6616)
  line L3 (-16.8984, 21.6616) -> (-16.8984, -21.6616)
loft "Loft34" add profiles "Sketch73", "Sketch74" section 1 section 2 separate body makes body 40
ref_plane "WorkPlane75" through (154.6, 0, 0) normal (1, 0, 0) x (0, 1, 0)
sketch "Sketch75" plane through (154.6, 0, 0) normal (1, 0, 0) x (0, 0, -1)
  line L0 (-17.1064, -21.8873) -> (-13.5485, -21.8873)
  line L1 (-13.5485, -21.8873) -> (-13.5485, 21.8873)
  line L2 (-13.5485, 21.8873) -> (-17.1064, 21.8873)
  line L3 (-17.1064, 21.8873) -> (-17.1064, -21.8873)
ref_plane "WorkPlane76" through (167.0667, 0, 0) normal (1, 0, 0) x (0, 1, 0)
sketch "Sketch76" plane through (167.0667, 0, 0) normal (1, 0, 0) x (0, 0, -1)
  line L0 (-13.8302, -18.336) -> (-10.8902, -18.336)
  line L1 (-10.8902, -18.336) -> (-10.8902, 18.336)
  line L2 (-10.8902, 18.336) -> (-13.8302, 18.336)
  line L3 (-13.8302, 18.336) -> (-13.8302, -18.336)
loft "Loft35" add profiles "Sketch75", "Sketch76" section 1 section 2 separate body makes body 41
ref_plane "WorkPlane77" through (166.2667, 0, 0) normal (1, 0, 0) x (0, 1, 0)
sketch "Sketch77" plane through (166.2667, 0, 0) normal (1, 0, 0) x (0, 0, -1)
  line L0 (-14.043, -18.5666) -> (-11.0608, -18.5666)
  line L1 (-11.0608, -18.5666) -> (-11.0608, 18.5666)
  line L2 (-11.0608, 18.5666) -> (-14.043, 18.5666)
  line L3 (-14.043, 18.5666) -> (-14.043, -18.5666)
ref_plane "WorkPlane78" through (178.7333, 0, 0) normal (1, 0, 0) x (0, 1, 0)
sketch "Sketch78" plane through (178.7333, 0, 0) normal (1, 0, 0) x (0, 0, -1)
  line L0 (-10.6604, -14.9089) -> (-8.4025, -14.9089)
  line L1 (-8.4025, -14.9089) -> (-8.4025, 14.9089)
  line L2 (-8.4025, 14.9089) -> (-10.6604, 14.9089)
  line L3 (-10.6604, 14.9089) -> (-10.6604, -14.9089)
loft "Loft36" add profiles "Sketch77", "Sketch78" section 1 section 2 separate body makes body 42
ref_plane "WorkPlane79" through (177.9333, 0, 0) normal (1, 0, 0) x (0, 1, 0)
sketch "Sketch79" plane through (177.9333, 0, 0) normal (1, 0, 0) x (0, 0, -1)
  line L0 (-10.883, -15.1492) -> (-8.573, -15.1492)
  line L1 (-8.573, -15.1492) -> (-8.573, 15.1492)
  line L2 (-8.573, 15.1492) -> (-10.883, 15.1492)
  line L3 (-10.883, 15.1492) -> (-10.883, -15.1492)
ref_plane "WorkPlane80" through (190, 0, 0) normal (1, 0, 0) x (0, 1, 0)
sketch "Sketch80" plane through (190, 0, 0) normal (1, 0, 0) x (0, 0, -1)
  line L0 (-7.2, -11.2) -> (-6, -11.2)
  line L1 (-6, -11.2) -> (-6, 11.2)
  line L2 (-6, 11.2) -> (-7.2, 11.2)
  line L3 (-7.2, 11.2) -> (-7.2, -11.2)
loft "Loft37" add profiles "Sketch79", "Sketch80" section 1 section 2 separate body makes body 43
ref_plane "WorkPlane81" through (-30, 0, 0) normal (1, 0, 0) x (0, 1, 0)
sketch "Sketch81" plane through (-30, 0, 0) normal (1, 0, 0) x (0, 0, -1)
  line L0 (11, -25.2) -> (12.2, -25.2)
  line L1 (12.2, -25.2) -> (12.2, 25.2)
  line L2 (12.2, 25.2) -> (11, 25.2)
  line L3 (11, 25.2) -> (11, -25.2)
ref_plane "WorkPlane82" through (-23.6, 0, 0) normal (1, 0, 0) x (0, 1, 0)
sketch "Sketch82" plane through (-23.6, 0, 0) normal (1, 0, 0) x (0, 0, -1)
  line L0 (13.8, -29.146) -> (17.346, -29.146)
  line L1 (17.346, -29.146) -> (17.346, 29.146)
  line L2 (17.346, 29.146) -> (13.8, 29.146)
  line L3 (13.8, 29.146) -> (13.8, -29.146)
loft "Loft38" add profiles "Sketch81", "Sketch82" section 1 section 2 separate body makes body 44
ref_plane "WorkPlane83" through (-24.4, 0, 0) normal (1, 0, 0) x (0, 1, 0)
sketch "Sketch83" plane through (-24.4, 0, 0) normal (1, 0, 0) x (0, 0, -1)
  line L0 (13.45, -28.8108) -> (16.8608, -28.8108)
  line L1 (16.8608, -28.8108) -> (16.8608, 28.8108)
  line L2 (16.8608, 28.8108) -> (13.45, 28.8108)
  line L3 (13.45, 28.8108) -> (13.45, -28.8108)
ref_plane "WorkPlane84" through (-21.6, 0, 0) normal (1, 0, 0) x (0, 1, 0)
sketch "Sketch84" plane through (-21.6, 0, 0) normal (1, 0, 0) x (0, 0, -1)
  line L0 (14.6091, -29.8371) -> (18.4462, -29.8371)
  line L1 (18.4462, -29.8371) -> (18.4462, 29.8371)
  line L2 (18.4462, 29.8371) -> (14.6091, 29.8371)
  line L3 (14.6091, 29.8371) -> (14.6091, -29.8371)
loft "Loft39" add profiles "Sketch83", "Sketch84" section 1 section 2 separate body makes body 45
ref_plane "WorkPlane85" through (-22.4, 0, 0) normal (1, 0, 0) x (0, 1, 0)
sketch "Sketch85" plane through (-22.4, 0, 0) normal (1, 0, 0) x (0, 0, -1)
  line L0 (14.325, -29.6278) -> (18.0528, -29.6278)
  line L1 (18.0528, -29.6278) -> (18.0528, 29.6278)
  line L2 (18.0528, 29.6278) -> (14.325, 29.6278)
  line L3 (14.325, 29.6278) -> (14.325, -29.6278)
ref_plane "WorkPlane86" through (-17.6, 0, 0) normal (1, 0, 0) x (0, 1, 0)
sketch "Sketch86" plane through (-17.6, 0, 0) normal (1, 0, 0) x (0, 0, -1)
  line L0 (15.7, -30.2773) -> (19.9773, -30.2773)
  line L1 (19.9773, -30.2773) -> (19.9773, 30.2773)
  line L2 (19.9773, 30.2773) -> (15.7, 30.2773)
  line L3 (15.7, 30.2773) -> (15.7, -30.2773)
loft "Loft40" add profiles "Sketch85", "Sketch86" section 1 section 2 separate body makes body 46
ref_plane "WorkPlane87" through (-18.4, 0, 0) normal (1, 0, 0) x (0, 1, 0)
sketch "Sketch87" plane through (-18.4, 0, 0) normal (1, 0, 0) x (0, 0, -1)
  line L0 (15.4818, -30.2013) -> (19.6832, -30.2013)
  line L1 (19.6832, -30.2013) -> (19.6832, 30.2013)
  line L2 (19.6832, 30.2013) -> (15.4818, 30.2013)
  line L3 (15.4818, 30.2013) -> (15.4818, -30.2013)
ref_plane "WorkPlane88" through (-11.6, 0, 0) normal (1, 0, 0) x (0, 1, 0)
sketch "Sketch88" plane through (-11.6, 0, 0) normal (1, 0, 0) x (0, 0, -1)
  line L0 (17.3364, -30.7044) -> (22.0408, -30.7044)
  line L1 (22.0408, -30.7044) -> (22.0408, 30.7044)
  line L2 (22.0408, 30.7044) -> (17.3364, 30.7044)
  line L3 (17.3364, 30.7044) -> (17.3364, -30.7044)
loft "Loft41" add profiles "Sketch87", "Sketch88" section 1 section 2 separate body makes body 47
ref_plane "WorkPlane89" through (-12.4, 0, 0) normal (1, 0, 0) x (0, 1, 0)
sketch "Sketch89" plane through (-12.4, 0, 0) normal (1, 0, 0) x (0, 0, -1)
  line L0 (17.1182, -30.6602) -> (21.7784, -30.6602)
  line L1 (21.7784, -30.6602) -> (21.7784, 30.6602)
  line L2 (21.7784, 30.6602) -> (17.1182, 30.6602)
  line L3 (17.1182, 30.6602) -> (17.1182, -30.6602)
ref_plane "WorkPlane90" through (-5.6, 0, 0) normal (1, 0, 0) x (0, 1, 0)
sketch "Sketch90" plane through (-5.6, 0, 0) normal (1, 0, 0) x (0, 0, -1)
  line L0 (18.9727, -30.9332) -> (23.9059, -30.9332)
  line L1 (23.9059, -30.9332) -> (23.9059, 30.9332)
  line L2 (23.9059, 30.9332) -> (18.9727, 30.9332)
  line L3 (18.9727, 30.9332) -> (18.9727, -30.9332)
loft "Loft42" add profiles "Sketch89", "Sketch90" section 1 section 2 separate body makes body 48
ref_plane "WorkPlane91" through (-6.4, 0, 0) normal (1, 0, 0) x (0, 1, 0)
sketch "Sketch91" plane through (-6.4, 0, 0) normal (1, 0, 0) x (0, 0, -1)
  line L0 (18.7545, -30.9125) -> (23.6671, -30.9125)
  line L1 (23.6671, -30.9125) -> (23.6671, 30.9125)
  line L2 (23.6671, 30.9125) -> (18.7545, 30.9125)
  line L3 (18.7545, 30.9125) -> (18.7545, -30.9125)
ref_plane "WorkPlane92" through (0.4, 0, 0) normal (1, 0, 0) x (0, 1, 0)
sketch "Sketch92" plane through (0.4, 0, 0) normal (1, 0, 0) x (0, 0, -1)
  line L0 (20.5, -31) -> (25.5, -31)
  line L1 (25.5, -31) -> (25.5, 31)
  line L2 (25.5, 31) -> (20.5, 31)
  line L3 (20.5, 31) -> (20.5, -31)
loft "Loft43" add profiles "Sketch91", "Sketch92" section 1 section 2 separate body makes body 49
ref_plane "WorkPlane93" through (-0.4, 0, 0) normal (1, 0, 0) x (0, 1, 0)
sketch "Sketch93" plane through (-0.4, 0, 0) normal (1, 0, 0) x (0, 0, -1)
  line L0 (20.3909, -30.9997) -> (25.3906, -30.9997)
  line L1 (25.3906, -30.9997) -> (25.3906, 30.9997)
  line L2 (25.3906, 30.9997) -> (20.3909, 30.9997)
  line L3 (20.3909, 30.9997) -> (20.3909, -30.9997)
ref_plane "WorkPlane94" through (30.4, 0, 0) normal (1, 0, 0) x (0, 1, 0)
sketch "Sketch94" plane through (30.4, 0, 0) normal (1, 0, 0) x (0, 0, -1)
  line L0 (20.5, -31) -> (25.5, -31)
  line L1 (25.5, -31) -> (25.5, 31)
  line L2 (25.5, 31) -> (20.5, 31)
  line L3 (20.5, 31) -> (20.5, -31)
loft "Loft44" add profiles "Sketch93", "Sketch94" section 1 section 2 separate body makes body 50
ref_plane "WorkPlane95" through (29.6, 0, 0) normal (1, 0, 0) x (0, 1, 0)
sketch "Sketch95" plane through (29.6, 0, 0) normal (1, 0, 0) x (0, 0, -1)
  line L0 (20.5, -31) -> (25.5, -31)
  line L1 (25.5, -31) -> (25.5, 31)
  line L2 (25.5, 31) -> (20.5, 31)
  line L3 (20.5, 31) -> (20.5, -31)
ref_plane "WorkPlane96" through (60.4, 0, 0) normal (1, 0, 0) x (0, 1, 0)
sketch "Sketch96" plane through (60.4, 0, 0) normal (1, 0, 0) x (0, 0, -1)
  line L0 (20.5, -31) -> (25.5, -31)
  line L1 (25.5, -31) -> (25.5, 31)
  line L2 (25.5, 31) -> (20.5, 31)
  line L3 (20.5, 31) -> (20.5, -31)
loft "Loft45" add profiles "Sketch95", "Sketch96" section 1 section 2 separate body makes body 51
ref_plane "WorkPlane97" through (59.6, 0, 0) normal (1, 0, 0) x (0, 1, 0)
sketch "Sketch97" plane through (59.6, 0, 0) normal (1, 0, 0) x (0, 0, -1)
  line L0 (20.5, -31) -> (25.5, -31)
  line L1 (25.5, -31) -> (25.5, 31)
  line L2 (25.5, 31) -> (20.5, 31)
  line L3 (20.5, 31) -> (20.5, -31)
ref_plane "WorkPlane98" through (90.4, 0, 0) normal (1, 0, 0) x (0, 1, 0)
sketch "Sketch98" plane through (90.4, 0, 0) normal (1, 0, 0) x (0, 0, -1)
  line L0 (20.5, -31) -> (25.5, -31)
  line L1 (25.5, -31) -> (25.5, 31)
  line L2 (25.5, 31) -> (20.5, 31)
  line L3 (20.5, 31) -> (20.5, -31)
loft "Loft46" add profiles "Sketch97", "Sketch98" section 1 section 2 separate body makes body 52
ref_plane "WorkPlane99" through (89.6, 0, 0) normal (1, 0, 0) x (0, 1, 0)
sketch "Sketch99" plane through (89.6, 0, 0) normal (1, 0, 0) x (0, 0, -1)
  line L0 (20.5, -31) -> (25.5, -31)
  line L1 (25.5, -31) -> (25.5, 31)
  line L2 (25.5, 31) -> (20.5, 31)
  line L3 (20.5, 31) -> (20.5, -31)
ref_plane "WorkPlane100" through (120.4, 0, 0) normal (1, 0, 0) x (0, 1, 0)
sketch "Sketch100" plane through (120.4, 0, 0) normal (1, 0, 0) x (0, 0, -1)
  line L0 (20.5, -30.9848) -> (25.4848, -30.9848)
  line L1 (25.4848, -30.9848) -> (25.4848, 30.9848)
  line L2 (25.4848, 30.9848) -> (20.5, 30.9848)
  line L3 (20.5, 30.9848) -> (20.5, -30.9848)
loft "Loft47" add profiles "Sketch99", "Sketch100" section 1 section 2 separate body makes body 53
ref_plane "WorkPlane101" through (119.6, 0, 0) normal (1, 0, 0) x (0, 1, 0)
sketch "Sketch101" plane through (119.6, 0, 0) normal (1, 0, 0) x (0, 0, -1)
  line L0 (20.5, -31) -> (25.5, -31)
  line L1 (25.5, -31) -> (25.5, 31)
  line L2 (25.5, 31) -> (20.5, 31)
  line L3 (20.5, 31) -> (20.5, -31)
ref_plane "WorkPlane102" through (122.4, 0, 0) normal (1, 0, 0) x (0, 1, 0)
sketch "Sketch102" plane through (122.4, 0, 0) normal (1, 0, 0) x (0, 0, -1)
  line L0 (20.4147, -30.8142) -> (25.323, -30.8142)
  line L1 (25.323, -30.8142) -> (25.323, 30.8142)
  line L2 (25.323, 30.8142) -> (20.4147, 30.8142)
  line L3 (20.4147, 30.8142) -> (20.4147, -30.8142)
loft "Loft48" add profiles "Sketch101", "Sketch102" section 1 section 2 separate body makes body 54
ref_plane "WorkPlane103" through (121.6, 0, 0) normal (1, 0, 0) x (0, 1, 0)
sketch "Sketch103" plane through (121.6, 0, 0) normal (1, 0, 0) x (0, 0, -1)
  line L0 (20.5, -30.939) -> (25.439, -30.939)
  line L1 (25.439, -30.939) -> (25.439, 30.939)
  line L2 (25.439, 30.939) -> (20.5, 30.939)
  line L3 (20.5, 30.939) -> (20.5, -30.939)
ref_plane "WorkPlane104" through (132.0667, 0, 0) normal (1, 0, 0) x (0, 1, 0)
sketch "Sketch104" plane through (132.0667, 0, 0) normal (1, 0, 0) x (0, 0, -1)
  line L0 (18.3534, -28.16) -> (22.8821, -28.16)
  line L1 (22.8821, -28.16) -> (22.8821, 28.16)
  line L2 (22.8821, 28.16) -> (18.3534, 28.16)
  line L3 (18.3534, 28.16) -> (18.3534, -28.16)
loft "Loft49" add profiles "Sketch103", "Sketch104" section 1 section 2 separate body makes body 55
ref_plane "WorkPlane105" through (131.2667, 0, 0) normal (1, 0, 0) x (0, 1, 0)
sketch "Sketch105" plane through (131.2667, 0, 0) normal (1, 0, 0) x (0, 0, -1)
  line L0 (18.524, -28.3803) -> (23.0848, -28.3803)
  line L1 (23.0848, -28.3803) -> (23.0848, 28.3803)
  line L2 (23.0848, 28.3803) -> (18.524, 28.3803)
  line L3 (18.524, 28.3803) -> (18.524, -28.3803)
ref_plane "WorkPlane106" through (143.7333, 0, 0) normal (1, 0, 0) x (0, 1, 0)
sketch "Sketch106" plane through (143.7333, 0, 0) normal (1, 0, 0) x (0, 0, -1)
  line L0 (15.8657, -24.9301) -> (19.9095, -24.9301)
  line L1 (19.9095, -24.9301) -> (19.9095, 24.9301)
  line L2 (19.9095, 24.9301) -> (15.8657, 24.9301)
  line L3 (15.8657, 24.9301) -> (15.8657, -24.9301)
loft "Loft50" add profiles "Sketch105", "Sketch106" section 1 section 2 separate body makes body 56
ref_plane "WorkPlane107" through (142.9333, 0, 0) normal (1, 0, 0) x (0, 1, 0)
sketch "Sketch107" plane through (142.9333, 0, 0) normal (1, 0, 0) x (0, 0, -1)
  line L0 (16.0363, -25.1527) -> (20.1144, -25.1527)
  line L1 (20.1144, -25.1527) -> (20.1144, 25.1527)
  line L2 (20.1144, 25.1527) -> (16.0363, 25.1527)
  line L3 (16.0363, 25.1527) -> (16.0363, -25.1527)
ref_plane "WorkPlane108" through (155.4, 0, 0) normal (1, 0, 0) x (0, 1, 0)
sketch "Sketch108" plane through (155.4, 0, 0) normal (1, 0, 0) x (0, 0, -1)
  line L0 (13.3779, -21.6616) -> (16.8984, -21.6616)
  line L1 (16.8984, -21.6616) -> (16.8984, 21.6616)
  line L2 (16.8984, 21.6616) -> (13.3779, 21.6616)
  line L3 (13.3779, 21.6616) -> (13.3779, -21.6616)
loft "Loft51" add profiles "Sketch107", "Sketch108" section 1 section 2 separate body makes body 57
ref_plane "WorkPlane109" through (154.6, 0, 0) normal (1, 0, 0) x (0, 1, 0)
sketch "Sketch109" plane through (154.6, 0, 0) normal (1, 0, 0) x (0, 0, -1)
  line L0 (13.5485, -21.8873) -> (17.1064, -21.8873)
  line L1 (17.1064, -21.8873) -> (17.1064, 21.8873)
  line L2 (17.1064, 21.8873) -> (13.5485, 21.8873)
  line L3 (13.5485, 21.8873) -> (13.5485, -21.8873)
ref_plane "WorkPlane110" through (167.0667, 0, 0) normal (1, 0, 0) x (0, 1, 0)
sketch "Sketch110" plane through (167.0667, 0, 0) normal (1, 0, 0) x (0, 0, -1)
  line L0 (10.8902, -18.336) -> (13.8302, -18.336)
  line L1 (13.8302, -18.336) -> (13.8302, 18.336)
  line L2 (13.8302, 18.336) -> (10.8902, 18.336)
  line L3 (10.8902, 18.336) -> (10.8902, -18.336)
loft "Loft52" add profiles "Sketch109", "Sketch110" section 1 section 2 separate body makes body 58
ref_plane "WorkPlane111" through (166.2667, 0, 0) normal (1, 0, 0) x (0, 1, 0)
sketch "Sketch111" plane through (166.2667, 0, 0) normal (1, 0, 0) x (0, 0, -1)
  line L0 (11.0608, -18.5666) -> (14.043, -18.5666)
  line L1 (14.043, -18.5666) -> (14.043, 18.5666)
  line L2 (14.043, 18.5666) -> (11.0608, 18.5666)
  line L3 (11.0608, 18.5666) -> (11.0608, -18.5666)
ref_plane "WorkPlane112" through (178.7333, 0, 0) normal (1, 0, 0) x (0, 1, 0)
sketch "Sketch112" plane through (178.7333, 0, 0) normal (1, 0, 0) x (0, 0, -1)
  line L0 (8.4025, -14.9089) -> (10.6604, -14.9089)
  line L1 (10.6604, -14.9089) -> (10.6604, 14.9089)
  line L2 (10.6604, 14.9089) -> (8.4025, 14.9089)
  line L3 (8.4025, 14.9089) -> (8.4025, -14.9089)
loft "Loft53" add profiles "Sketch111", "Sketch112" section 1 section 2 separate body makes body 59
ref_plane "WorkPlane113" through (177.9333, 0, 0) normal (1, 0, 0) x (0, 1, 0)
sketch "Sketch113" plane through (177.9333, 0, 0) normal (1, 0, 0) x (0, 0, -1)
  line L0 (8.573, -15.1492) -> (10.883, -15.1492)
  line L1 (10.883, -15.1492) -> (10.883, 15.1492)
  line L2 (10.883, 15.1492) -> (8.573, 15.1492)
  line L3 (8.573, 15.1492) -> (8.573, -15.1492)
ref_plane "WorkPlane114" through (190, 0, 0) normal (1, 0, 0) x (0, 1, 0)
sketch "Sketch114" plane through (190, 0, 0) normal (1, 0, 0) x (0, 0, -1)
  line L0 (6, -11.2) -> (7.2, -11.2)
  line L1 (7.2, -11.2) -> (7.2, 11.2)
  line L2 (7.2, 11.2) -> (6, 11.2)
  line L3 (6, 11.2) -> (6, -11.2)
loft "Loft54" add profiles "Sketch113", "Sketch114" section 1 section 2 separate body makes body 60
ref_plane "WorkPlane115" through (-30, 0, 0) normal (1, 0, 0) x (0, 1, 0)
sketch "Sketch115" plane through (-30, 0, 0) normal (1, 0, 0) x (0, 0, -1)
  line L0 (-11, 24) -> (11, 24)
  line L1 (11, 24) -> (11, 25.2)
  line L2 (11, 25.2) -> (-11, 25.2)
  line L3 (-11, 25.2) -> (-11, 24)
ref_plane "WorkPlane116" through (-23.6, 0, 0) normal (1, 0, 0) x (0, 1, 0)
sketch "Sketch116" plane through (-23.6, 0, 0) normal (1, 0, 0) x (0, 0, -1)
  line L0 (-13.8, 25.6) -> (13.8, 25.6)
  line L1 (13.8, 25.6) -> (13.8, 29.146)
  line L2 (13.8, 29.146) -> (-13.8, 29.146)
  line L3 (-13.8, 29.146) -> (-13.8, 25.6)
loft "Loft55" add profiles "Sketch115", "Sketch116" section 1 section 2 separate body makes body 61
ref_plane "WorkPlane117" through (-24.4, 0, 0) normal (1, 0, 0) x (0, 1, 0)
sketch "Sketch117" plane through (-24.4, 0, 0) normal (1, 0, 0) x (0, 0, -1)
  line L0 (-13.45, 25.4) -> (13.45, 25.4)
  line L1 (13.45, 25.4) -> (13.45, 28.8108)
  line L2 (13.45, 28.8108) -> (-13.45, 28.8108)
  line L3 (-13.45, 28.8108) -> (-13.45, 25.4)
ref_plane "WorkPlane118" through (-21.6, 0, 0) normal (1, 0, 0) x (0, 1, 0)
sketch "Sketch118" plane through (-21.6, 0, 0) normal (1, 0, 0) x (0, 0, -1)
  line L0 (-14.6091, 26) -> (14.6091, 26)
  line L1 (14.6091, 26) -> (14.6091, 29.8371)
  line L2 (14.6091, 29.8371) -> (-14.6091, 29.8371)
  line L3 (-14.6091, 29.8371) -> (-14.6091, 26)
loft "Loft56" add profiles "Sketch117", "Sketch118" section 1 section 2 separate body makes body 62
ref_plane "WorkPlane119" through (-22.4, 0, 0) normal (1, 0, 0) x (0, 1, 0)
sketch "Sketch119" plane through (-22.4, 0, 0) normal (1, 0, 0) x (0, 0, -1)
  line L0 (-14.325, 25.9) -> (14.325, 25.9)
  line L1 (14.325, 25.9) -> (14.325, 29.6278)
  line L2 (14.325, 29.6278) -> (-14.325, 29.6278)
  line L3 (-14.325, 29.6278) -> (-14.325, 25.9)
ref_plane "WorkPlane120" through (-17.6, 0, 0) normal (1, 0, 0) x (0, 1, 0)
sketch "Sketch120" plane through (-17.6, 0, 0) normal (1, 0, 0) x (0, 0, -1)
  line L0 (-15.7, 26) -> (15.7, 26)
  line L1 (15.7, 26) -> (15.7, 30.2773)
  line L2 (15.7, 30.2773) -> (-15.7, 30.2773)
  line L3 (-15.7, 30.2773) -> (-15.7, 26)
loft "Loft57" add profiles "Sketch119", "Sketch120" section 1 section 2 separate body makes body 63
ref_plane "WorkPlane121" through (-18.4, 0, 0) normal (1, 0, 0) x (0, 1, 0)
sketch "Sketch121" plane through (-18.4, 0, 0) normal (1, 0, 0) x (0, 0, -1)
  line L0 (-15.4818, 26) -> (15.4818, 26)
  line L1 (15.4818, 26) -> (15.4818, 30.2013)
  line L2 (15.4818, 30.2013) -> (-15.4818, 30.2013)
  line L3 (-15.4818, 30.2013) -> (-15.4818, 26)
ref_plane "WorkPlane122" through (-11.6, 0, 0) normal (1, 0, 0) x (0, 1, 0)
sketch "Sketch122" plane through (-11.6, 0, 0) normal (1, 0, 0) x (0, 0, -1)
  line L0 (-17.3364, 26) -> (17.3364, 26)
  line L1 (17.3364, 26) -> (17.3364, 30.7044)
  line L2 (17.3364, 30.7044) -> (-17.3364, 30.7044)
  line L3 (-17.3364, 30.7044) -> (-17.3364, 26)
loft "Loft58" add profiles "Sketch121", "Sketch122" section 1 section 2 separate body makes body 64
ref_plane "WorkPlane123" through (-12.4, 0, 0) normal (1, 0, 0) x (0, 1, 0)
sketch "Sketch123" plane through (-12.4, 0, 0) normal (1, 0, 0) x (0, 0, -1)
  line L0 (-17.1182, 26) -> (17.1182, 26)
  line L1 (17.1182, 26) -> (17.1182, 30.6602)
  line L2 (17.1182, 30.6602) -> (-17.1182, 30.6602)
  line L3 (-17.1182, 30.6602) -> (-17.1182, 26)
ref_plane "WorkPlane124" through (-5.6, 0, 0) normal (1, 0, 0) x (0, 1, 0)
sketch "Sketch124" plane through (-5.6, 0, 0) normal (1, 0, 0) x (0, 0, -1)
  line L0 (-18.9727, 26) -> (18.9727, 26)
  line L1 (18.9727, 26) -> (18.9727, 30.9332)
  line L2 (18.9727, 30.9332) -> (-18.9727, 30.9332)
  line L3 (-18.9727, 30.9332) -> (-18.9727, 26)
loft "Loft59" add profiles "Sketch123", "Sketch124" section 1 section 2 separate body makes body 65
ref_plane "WorkPlane125" through (-6.4, 0, 0) normal (1, 0, 0) x (0, 1, 0)
sketch "Sketch125" plane through (-6.4, 0, 0) normal (1, 0, 0) x (0, 0, -1)
  line L0 (-18.7545, 26) -> (18.7545, 26)
  line L1 (18.7545, 26) -> (18.7545, 30.9125)
  line L2 (18.7545, 30.9125) -> (-18.7545, 30.9125)
  line L3 (-18.7545, 30.9125) -> (-18.7545, 26)
ref_plane "WorkPlane126" through (0.4, 0, 0) normal (1, 0, 0) x (0, 1, 0)
sketch "Sketch126" plane through (0.4, 0, 0) normal (1, 0, 0) x (0, 0, -1)
  line L0 (-20.5, 26) -> (20.5, 26)
  line L1 (20.5, 26) -> (20.5, 31)
  line L2 (20.5, 31) -> (-20.5, 31)
  line L3 (-20.5, 31) -> (-20.5, 26)
loft "Loft60" add profiles "Sketch125", "Sketch126" section 1 section 2 separate body makes body 66
ref_plane "WorkPlane127" through (-0.4, 0, 0) normal (1, 0, 0) x (0, 1, 0)